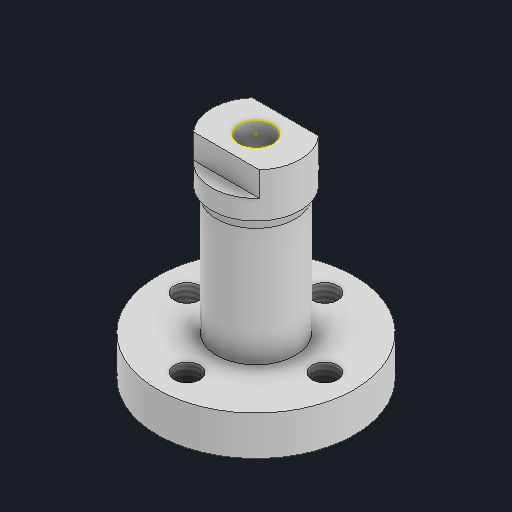
# Autodesk Inventor part: trục (1)
Saved by Autodesk Inventor 2027 (Build 310192060, 192F)
## iProperties
Created: 2025-07-18
Part Number: trục (1)
Material: Generic
Document SubType Name: Modeling
Designer: Laptop
Density: 1 g/cm^3
Appearance: Default
Author: Laptop
Autodesk Inventor part; units mm, degrees
ref_plane "YZ Plane" through (0, 0, 0) normal (1, 0, 0) x (0, 1, 0)
ref_plane "Work Plane3" through (3.365, 12.4, 4.8607) normal (0, 0, -1) x (-1, 0, 0)
sketch "Sketch2" plane through (3.365, 12.4, 4.8607) normal (0, 0, -1) x (-1, 0, 0)
  line L0 (7.9404, 0) -> (14.9404, 0)
  line L1 (7.9404, 0) -> (7.9404, 4)
  line L2 (13.9404, 5.125) -> (13.9404, 16)
  line L3 (13.4404, 17) -> (13.4404, 21.5)
  line L4 (13.4404, 21.5) -> (15.9404, 21.5)
  line L5 (13.4404, 17) -> (13.9404, 16)
  line L6 (17.9403, 0) -> (17.9403, 16.6253)
  line L7 (15.9404, 21.5) -> (16.1904, 21.5)
  line L8 (16.1904, 21.5) -> (16.1904, 10)
  line L9 (16.1904, 4) -> (16.1904, 10)
  line L10 (13.9404, 5.125) -> (13.9404, 4)
  line L11 (13.9404, 4) -> (7.9404, 4)
  line L12 (16.1904, 4) -> (16.1904, 0)
  line L13 (16.1904, 0) -> (14.9404, 0)
  line L14 (13.9404, 4) -> (13.9404, 16)
  dimension "d6" = 4
  dimension "d38" = 0.25
  dimension "d40" = 12
  constraints: 30 end point, 4 vertical, 3 perpendicular, 2 horizontal, 2 point on line, 1 parallel
  measures "d6" distance of L0.start L1.end
  measures "d38" distance of L4.end L7.end
  measures "d40" distance of L10.end L14.end
revolve "Revolution1" add sketch "Sketch2" angle 360 about axis through (-14.5752, 12.4, 4.8607) along (0, 1, 0)
sketch "Sketch3" plane through (-14.5752, 12.4, 4.8607) normal (0, -1, 0) x (1, 0, 0)
  line L0 (0, 0) -> (-7, 0)
  circle A0 centre (-7, 0) radius 1.3
  circle A1 centre (0, -7) radius 1.3
  circle A2 centre (7, 0) radius 1.3
  circle A3 centre (0, 7) radius 1.3
  point P0 (14.5753, -4.8607)
  dimension "d17" = 7
  dimension "d18" = 2.6
  dimension "d21" = 360
  constraints: 4 centre point, 2 end point, 1 coincident, 1 horizontal, 9 other
  measures "d17" distance of L0.start L0.end
  measures "d18" diameter of A0
extrude "Extrusion2" cut sketch "Sketch3" against normal blind 4
thread "Thread1" size "M3x0.5" class "6H" standard "ANSI Metric M Profile" full length
thread "Thread2" size "M3x0.5" class "6H" standard "ANSI Metric M Profile" full length
thread "Thread3" size "M3x0.5" class "6H" standard "ANSI Metric M Profile" full length
thread "Thread4" size "M3x0.5" class "6H" standard "ANSI Metric M Profile" full length
ref_plane "Work Plane5" through (-14.5752, 33.9, 4.8607) normal (0, 1, 0) x (1, 0, 0)
sketch "Sketch5" plane through (-14.5752, 33.9, 4.8607) normal (0, 1, 0) x (1, 0, 0)
  line L0 (0, 0) -> (0, -3)
  line L1 (0, 0) -> (0, 3)
  circle A0 centre (0, 0) radius 4.4999 projected
  line L2 (0, -3) -> (-3.3539, -3)
  line L3 (0, -3) -> (3.3539, -3)
  line L4 (0, 3) -> (-3.3539, 3)
  line L5 (0, 3) -> (3.3539, 3)
  point P0 (14.5752, 4.8607)
  dimension "d42" = 3
  dimension "d43" = 3
  constraints: 12 end point, 4 point on circle, 2 horizontal, 2 point on line, 2 vertical
  measures "d42" distance of L0.start L0.end
  measures "d43" distance of L0.start L1.end
extrude "Extrusion4" cut sketch "Sketch5" against normal blind 2.5 contours L3 A0 L2 | L4 A0 L5
sketch "Sketch6" plane through (-14.5752, 33.9, 4.8607) normal (0, 1, 0) x (1, 0, 0)
  circle A0 centre (0, 0) radius 1.7499 projected
body "Solid1"
